GBA Case Wall Mount (Autodesk Fusion 360 design; units mm, degrees)
Autodesk Fusion 360 part; units mm, degrees
sketch "Sketch1" plane through (0, 0, 0) normal (0, 1, 0) x (1, 0, 0)
  line L0 (61, -57.75) -> (-61, -57.75)
  line L1 (-61, -57.75) -> (-61, 57.75)
  line L2 (-61, 57.75) -> (61, 57.75)
  line L3 (61, 57.75) -> (61, -57.75)
  line L4 (61, -57.75) -> (-61, 57.75) construction
  line L5 (-61, -57.75) -> (61, 57.75) construction
  dimension "d1" = 122
  dimension "d2" = 115.5
  constraint perpendicular L0 L1
  constraint parallel L0 L2
  constraint parallel L1 L3
  constraint horizontal L0
  constraint coincident L4 origin
  constraint coincident L5 origin
  measures "d1" distance of L1.end L2.end
  measures "d2" distance of L0.end L1.end
extrude "Extrude1" add sketch "Sketch1" along normal blind 2
sketch "Sketch2" plane through (0, 2, 0) normal (0, 1, 0) x (-1, 0, 0)
  line L0 (-61, -57.75) -> (61, -57.75)
  line L1 (61, -57.75) -> (61, 57.75)
  line L2 (61, 57.75) -> (-61, 57.75)
  line L3 (-61, 57.75) -> (-61, -57.75)
  line L4 (61, 57.75) -> (0.7, 57.75)
  line L5 (0.7, 57.75) -> (0.7, 19.25)
  line L6 (0.7, 19.25) -> (61, 19.25)
  line L7 (61, 19.25) -> (61, 57.75)
  line L8 (-61, 57.75) -> (-0.7, 57.75)
  line L9 (-0.7, 57.75) -> (-0.7, 19.25)
  line L10 (-0.7, 19.25) -> (-61, 19.25)
  line L11 (-61, 19.25) -> (-61, 57.75)
  line L12 (61, 19.25) -> (0.7, 19.25)
  line L13 (0.7, 19.25) -> (0.7, -19.25)
  line L14 (0.7, -19.25) -> (61, -19.25)
  line L15 (61, -19.25) -> (61, 19.25)
  line L16 (61, -19.25) -> (0.7, -19.25)
  line L17 (0.7, -19.25) -> (0.7, -57.75)
  line L18 (0.7, -57.75) -> (61, -57.75)
  line L19 (61, -57.75) -> (61, -19.25)
  line L20 (-61, 19.25) -> (-0.7, 19.25)
  line L21 (-0.7, 19.25) -> (-0.7, -19.25)
  line L22 (-0.7, -19.25) -> (-61, -19.25)
  line L23 (-61, -19.25) -> (-61, 19.25)
  line L24 (-61, -19.25) -> (-0.7, -19.25)
  line L25 (-0.7, -19.25) -> (-0.7, -57.75)
  line L26 (-0.7, -57.75) -> (-61, -57.75)
  line L27 (-61, -57.75) -> (-61, -19.25)
  line L28 (61, 57.75) -> (0.7, 57.75)
  line L29 (0.7, 57.75) -> (0.7, 56.25)
  line L30 (0.7, 56.25) -> (61, 56.25)
  line L31 (61, 56.25) -> (61, 57.75)
  line L32 (61, 19.25) -> (0.7, 19.25)
  line L33 (0.7, 19.25) -> (0.7, 17.75)
  line L34 (0.7, 17.75) -> (61, 17.75)
  line L35 (61, 17.75) -> (61, 19.25)
  line L36 (61, -19.25) -> (0.7, -19.25)
  line L37 (0.7, -19.25) -> (0.7, -20.75)
  line L38 (0.7, -20.75) -> (61, -20.75)
  line L39 (61, -20.75) -> (61, -19.25)
  line L40 (-61, -19.25) -> (-0.7, -19.25)
  line L41 (-0.7, -19.25) -> (-0.7, -20.75)
  line L42 (-0.7, -20.75) -> (-61, -20.75)
  line L43 (-61, -20.75) -> (-61, -19.25)
  line L44 (-61, 19.25) -> (-0.7, 19.25)
  line L45 (-0.7, 19.25) -> (-0.7, 17.75)
  line L46 (-0.7, 17.75) -> (-61, 17.75)
  line L47 (-61, 17.75) -> (-61, 19.25)
  line L48 (-61, 57.75) -> (-0.7, 57.75)
  line L49 (-0.7, 57.75) -> (-0.7, 56.25)
  line L50 (-0.7, 56.25) -> (-61, 56.25)
  line L51 (-61, 56.25) -> (-61, 57.75)
  line L52 (61, 57.75) -> (59.35, 57.75)
  line L53 (59.35, 57.75) -> (59.35, 56.25)
  line L54 (59.35, 56.25) -> (61, 56.25)
  line L55 (61, 56.25) -> (61, 57.75)
  line L56 (0.7, 57.75) -> (2.35, 57.75)
  line L57 (2.35, 57.75) -> (2.35, 56.25)
  line L58 (2.35, 56.25) -> (0.7, 56.25)
  line L59 (0.7, 56.25) -> (0.7, 57.75)
  line L60 (61, 19.25) -> (59.35, 19.25)
  line L61 (59.35, 19.25) -> (59.35, 17.75)
  line L62 (59.35, 17.75) -> (61, 17.75)
  line L63 (61, 17.75) -> (61, 19.25)
  line L64 (0.7, 19.25) -> (2.35, 19.25)
  line L65 (2.35, 19.25) -> (2.35, 17.75)
  line L66 (2.35, 17.75) -> (0.7, 17.75)
  line L67 (0.7, 17.75) -> (0.7, 19.25)
  line L68 (61, -19.25) -> (59.35, -19.25)
  line L69 (59.35, -19.25) -> (59.35, -20.75)
  line L70 (59.35, -20.75) -> (61, -20.75)
  line L71 (61, -20.75) -> (61, -19.25)
  line L72 (0.7, -19.25) -> (2.35, -19.25)
  line L73 (2.35, -19.25) -> (2.35, -20.75)
  line L74 (2.35, -20.75) -> (0.7, -20.75)
  line L75 (0.7, -20.75) -> (0.7, -19.25)
  line L76 (-0.7, -19.25) -> (-2.35, -19.25)
  line L77 (-2.35, -19.25) -> (-2.35, -20.75)
  line L78 (-2.35, -20.75) -> (-0.7, -20.75)
  line L79 (-0.7, -20.75) -> (-0.7, -19.25)
  line L80 (-61, -19.25) -> (-59.35, -19.25)
  line L81 (-59.35, -19.25) -> (-59.35, -20.75)
  line L82 (-59.35, -20.75) -> (-61, -20.75)
  line L83 (-61, -20.75) -> (-61, -19.25)
  line L84 (-61, 19.25) -> (-59.35, 19.25)
  line L85 (-59.35, 19.25) -> (-59.35, 17.75)
  line L86 (-59.35, 17.75) -> (-61, 17.75)
  line L87 (-61, 17.75) -> (-61, 19.25)
  line L88 (-0.7, 19.25) -> (-2.35, 19.25)
  line L89 (-2.35, 19.25) -> (-2.35, 17.75)
  line L90 (-2.35, 17.75) -> (-0.7, 17.75)
  line L91 (-0.7, 17.75) -> (-0.7, 19.25)
  line L92 (-0.7, 57.75) -> (-2.35, 57.75)
  line L93 (-2.35, 57.75) -> (-2.35, 56.25)
  line L94 (-2.35, 56.25) -> (-0.7, 56.25)
  line L95 (-0.7, 56.25) -> (-0.7, 57.75)
  line L96 (-61, 57.75) -> (-59.35, 57.75)
  line L97 (-59.35, 57.75) -> (-59.35, 56.25)
  line L98 (-59.35, 56.25) -> (-61, 56.25)
  line L99 (-61, 56.25) -> (-61, 57.75)
  dimension "d5" = 60.3
  dimension "d6" = 38.5
  dimension "d7" = 60.3
  dimension "d8" = 38.5
  dimension "d9" = 60.3
  dimension "d10" = 38.5
  dimension "d11" = 38.5
  dimension "d12" = 60.3
  dimension "d13" = 38.5
  dimension "d14" = 60.3
  dimension "d15" = 60.3
  dimension "d16" = 38.5
  dimension "d17" = 1.5
  dimension "d18" = 60.3
  dimension "d19" = 1.5
  dimension "d20" = 60.3
  dimension "d21" = 1.5
  dimension "d22" = 60.3
  dimension "d23" = 1.5
  dimension "d24" = 60.3
  dimension "d25" = 1.5
  dimension "d26" = 60.3
  dimension "d27" = 1.5
  dimension "d30" = 1.65
  dimension "d31" = 1.5
  dimension "d32" = 1.65
  dimension "d33" = 1.5
  dimension "d34" = 1.5
  dimension "d35" = 1.65
  dimension "d36" = 1.5
  dimension "d37" = 1.65
  dimension "d38" = 1.65
  dimension "d39" = 1.65
  dimension "d40" = 1.65
  dimension "d41" = 1.5
  dimension "d42" = 1.65
  dimension "d43" = 1.65
  dimension "d44" = 1.5
  dimension "d45" = 1.65
  dimension "d46" = 1.65
  dimension "d47" = 1.5
  dimension "d48" = 1.65
  constraint horizontal L4
  constraint vertical L5
  constraint horizontal L6
  constraint vertical L7
  constraint coincident L1.end L2.start
  constraint horizontal L8
  constraint vertical L9
  constraint horizontal L10
  constraint vertical L11
  constraint coincident L2.end L3.start
  constraint horizontal L12
  constraint vertical L13
  constraint horizontal L14
  constraint vertical L15
  constraint horizontal L16
  constraint vertical L17
  constraint horizontal L18
  constraint vertical L19
  constraint horizontal L20
  constraint vertical L21
  constraint horizontal L22
  constraint vertical L23
  constraint horizontal L24
  constraint vertical L25
  constraint horizontal L26
  constraint vertical L27
  constraint horizontal L28
  constraint vertical L29
  constraint horizontal L30
  constraint vertical L31
  constraint horizontal L32
  constraint vertical L33
  constraint horizontal L34
  constraint vertical L35
  constraint horizontal L36
  constraint vertical L37
  constraint horizontal L38
  constraint vertical L39
  constraint horizontal L40
  constraint vertical L41
  constraint horizontal L42
  constraint vertical L43
  constraint horizontal L44
  constraint vertical L45
  constraint horizontal L46
  constraint vertical L47
  constraint horizontal L48
  constraint vertical L49
  constraint horizontal L50
  constraint vertical L51
  constraint horizontal L52
  constraint vertical L53
  constraint horizontal L54
  constraint vertical L55
  constraint horizontal L56
  constraint vertical L57
  constraint horizontal L58
  constraint vertical L59
  constraint horizontal L60
  constraint vertical L61
  constraint horizontal L62
  constraint vertical L63
  constraint horizontal L64
  constraint vertical L65
  constraint horizontal L66
  constraint vertical L67
  constraint horizontal L68
  constraint vertical L69
  constraint horizontal L70
  constraint vertical L71
  constraint horizontal L72
  constraint vertical L73
  constraint horizontal L74
  constraint vertical L75
  constraint horizontal L76
  constraint vertical L77
  constraint horizontal L78
  constraint vertical L79
  constraint horizontal L80
  constraint vertical L81
  constraint horizontal L82
  constraint vertical L83
  constraint horizontal L84
  constraint vertical L85
  constraint horizontal L86
  constraint vertical L87
  constraint horizontal L88
  constraint vertical L89
  constraint horizontal L90
  constraint vertical L91
  constraint horizontal L92
  constraint vertical L93
  constraint horizontal L94
  constraint vertical L95
  constraint horizontal L96
  constraint vertical L97
  constraint horizontal L98
  constraint vertical L99
  measures "d5" distance of L1.end L4.end
  measures "d6" distance of L1.end L6.end
  measures "d7" distance of L2.end L8.end
  measures "d8" distance of L2.end L10.end
  measures "d9" distance of L6.end L5.end
  measures "d10" distance of L6.end L14.end
  measures "d11" distance of L14.end L0.end
  measures "d12" distance of L14.end L13.end
  measures "d13" distance of L10.end L22.end
  measures "d14" distance of L10.end L9.end
  measures "d15" distance of L22.end L21.end
  measures "d16" distance of L22.end L0.start
  measures "d17" distance of L1.end L30.end
  measures "d18" distance of L6.end L5.end
  measures "d19" distance of L6.end L34.end
  measures "d20" distance of L14.end L13.end
  measures "d21" distance of L14.end L38.end
  measures "d22" distance of L22.end L21.end
  measures "d23" distance of L22.end L42.end
  measures "d24" distance of L10.end L9.end
  measures "d25" distance of L10.end L46.end
  measures "d26" distance of L2.end L8.end
  measures "d27" distance of L2.end L50.end
  measures "d30" distance of L1.end L52.end
  measures "d31" distance of L1.end L30.end
  measures "d32" distance of L4.end L56.end
  measures "d33" distance of L4.end L29.end
  measures "d34" distance of L6.end L34.end
  measures "d35" distance of L6.end L60.end
  measures "d36" distance of L5.end L33.end
  measures "d37" distance of L5.end L64.end
  measures "d38" distance of L14.end L68.end
  measures "d39" distance of L13.end L72.end
  measures "d40" distance of L21.end L76.end
  measures "d41" distance of L21.end L41.end
  measures "d42" distance of L22.end L80.end
  measures "d43" distance of L10.end L84.end
  measures "d44" distance of L10.end L46.end
  measures "d45" distance of L9.end L88.end
  measures "d46" distance of L8.end L92.end
  measures "d47" distance of L8.end L49.end
  measures "d48" distance of L2.end L96.end
extrude "Extrude2" add sketch "Sketch2" along normal blind 7.6 contours L22 L24 L40 L42 L77 L81 | L14 L16 L36 L38 L69 L73 | L10 L20 L44 L46 L85 L89 | L6 L12 L32 L34 L61 L65 | L2 L8 L48 L50 L93 L97 | L2 L4 L28 L30 L53 L57
sketch "Sketch3" plane through (0, 0, 56.25) normal (0, 0, -1) x (-1, 0, 0)
  line L0 (-59.35, 2) -> (-2.35, 2)
  line L1 (-2.35, 2) -> (-2.35, 9.6)
  line L2 (-2.35, 9.6) -> (-59.35, 9.6)
  line L3 (-59.35, 9.6) -> (-59.35, 2)
  line L4 (-59.35, 9.6) -> (-57.2, 9.6)
  circle A0 centre (-56.2, 7.3) radius 1
  line L5 (-2.35, 9.6) -> (-5.5, 9.6)
  circle A1 centre (-5.5, 7.3) radius 1
  dimension "d49" = 2.15
  dimension "d55" = 2
  dimension "d58" = 3.15
  dimension "d59" = 2.3
  dimension "d60" = 2
  constraint coincident L2.end L3.start
  constraint coincident L1.end L2.start
  measures "d49" distance of L2.end L4.end
  measures "d55" diameter of A0
  measures "d58" distance of L1.end L5.end
  measures "d59" distance of L5.end A1.centre
  measures "d60" diameter of A1
ref_plane "WorkPlane1" through (30.85, 5.8, 54.25) normal (0, 0, -1) x (-1, 0, 0)
sketch "Sketch4" plane through (30.85, 5.8, 54.25) normal (0, 0, -1) x (1, 0, 0)
  circle A0 centre (-25.35, -1.5) radius 0.5
  circle A1 centre (25.35, -1.5) radius 0.5
  point P0 (-25.35, -1.5)
  point P1 (25.35, -1.5)
  dimension "d62" = 1
  dimension "d63" = 1
  constraint coincident P0 A0.centre
  constraint coincident P1 A1.centre
  measures "d62" diameter of A0
  measures "d63" diameter of A1
loft "Loft1" add profiles "Sketch3", "Sketch4" section 1 contours A0 section 2 contours A1
loft "Loft2" add profiles "Sketch3", "Sketch4" section 1 contours A1 section 2 contours A0
sketch "Sketch5" plane through (0, 0, 17.75) normal (0, 0, -1) x (-1, 0, 0)
  line L0 (-59.35, 2) -> (-2.35, 2)
  line L1 (-2.35, 2) -> (-2.35, 9.6)
  line L2 (-2.35, 9.6) -> (-59.35, 9.6)
  line L3 (-59.35, 9.6) -> (-59.35, 2)
  line L4 (-59.35, 9.6) -> (-56.2, 9.6)
  line L5 (-56.2, 9.6) -> (-56.2, 7.3)
  line L6 (-2.35, 9.6) -> (-5.5, 9.6)
  line L7 (-5.5, 9.6) -> (-5.5, 7.3)
  circle A0 centre (-56.2, 7.3) radius 1
  circle A1 centre (-5.5, 7.3) radius 1
  dimension "d64" = 3.15
  dimension "d65" = 2.3
  dimension "d66" = 3.15
  dimension "d67" = 2.3
  dimension "d68" = 2
  dimension "d69" = 2
  constraint coincident L2.end L3.start
  constraint coincident L1.end L2.start
  constraint coincident L5.end A0.centre
  constraint coincident L7.end A1.centre
  measures "d64" distance of L2.end L4.end
  measures "d65" distance of L4.end L5.end
  measures "d66" distance of L1.end L6.end
  measures "d67" distance of L6.end L7.end
  measures "d68" diameter of A0
  measures "d69" diameter of A1
sketch "Sketch6" plane through (0, 0, -20.75) normal (0, 0, -1) x (-1, 0, 0)
  line L0 (-59.35, 2) -> (-2.35, 2)
  line L1 (-2.35, 2) -> (-2.35, 9.6)
  line L2 (-2.35, 9.6) -> (-59.35, 9.6)
  line L3 (-59.35, 9.6) -> (-59.35, 2)
  line L4 (-59.35, 9.6) -> (-56.2, 9.6)
  line L5 (-56.2, 9.6) -> (-56.2, 7.3)
  circle A0 centre (-56.2, 7.3) radius 1
  circle A1 centre (-5.5, 7.3) radius 1
  circle A2 centre (-5.5, 7.3) radius 1
  circle A3 centre (-5.5, 7.3) radius 1
  point P0 (-56.2, 7.3)
  point P1 (-55.2, 7.3)
  point P2 (-5.5, 7.3)
  dimension "d70" = 3.15
  constraint coincident L2.end L3.start
  constraint coincident P0 L5.end
  constraint perpendicular L2 L5
  constraint coincident A0 P1
  constraint coincident P2 A1.centre
  measures "d70" distance of L2.end L4.end
sketch "Sketch7" plane through (0, 0, 56.25) normal (0, 0, -1) x (-1, 0, 0)
  line L0 (2.35, 2) -> (59.35, 2)
  line L1 (59.35, 2) -> (59.35, 9.6)
  line L2 (59.35, 9.6) -> (2.35, 9.6)
  line L3 (2.35, 9.6) -> (2.35, 2)
  line L4 (2.35, 9.6) -> (5.5, 9.6)
  line L5 (5.5, 9.6) -> (5.5, 7.3)
  line L6 (59.35, 9.6) -> (56.2, 9.6)
  line L7 (56.2, 9.6) -> (56.2, 7.3)
  circle A0 centre (5.5, 7.3) radius 1
  circle A1 centre (56.2, 7.3) radius 1
  dimension "d71" = 3.15
  dimension "d72" = 2.3
  dimension "d73" = 3.15
  dimension "d74" = 2.3
  dimension "d75" = 2
  dimension "d76" = 2
  constraint coincident L2.end L3.start
  constraint coincident L1.end L2.start
  constraint coincident L5.end A0.centre
  constraint coincident L7.end A1.centre
  measures "d71" distance of L2.end L4.end
  measures "d72" distance of L4.end L5.end
  measures "d73" distance of L1.end L6.end
  measures "d74" distance of L6.end L7.end
  measures "d75" diameter of A0
  measures "d76" diameter of A1
sketch "Sketch8" plane through (0, 0, 17.75) normal (0, 0, -1) x (-1, 0, 0)
  line L0 (2.35, 2) -> (59.35, 2)
  line L1 (59.35, 2) -> (59.35, 9.6)
  line L2 (59.35, 9.6) -> (2.35, 9.6)
  line L3 (2.35, 9.6) -> (2.35, 2)
  circle A0 centre (5.5, 7.3) radius 1
  circle A1 centre (5.5, 7.3) radius 1
  circle A2 centre (56.2, 7.3) radius 1
  circle A3 centre (56.2, 7.3) radius 1
  point P0 (5.5, 7.3)
  point P1 (56.2, 7.3)
  constraint coincident P0 A0.centre
  constraint coincident P1 A2.centre
sketch "Sketch9" plane through (0, 0, -20.75) normal (0, 0, -1) x (-1, 0, 0)
  line L0 (2.35, 2) -> (59.35, 2)
  line L1 (59.35, 2) -> (59.35, 9.6)
  line L2 (59.35, 9.6) -> (2.35, 9.6)
  line L3 (2.35, 9.6) -> (2.35, 2)
  circle A0 centre (5.5, 7.3) radius 1
  circle A1 centre (5.5, 7.3) radius 1
  circle A2 centre (56.2, 7.3) radius 1
  circle A3 centre (56.2, 7.3) radius 1
  point P0 (5.5, 7.3)
  point P1 (56.2, 7.3)
  constraint coincident P0 A0.centre
  constraint coincident P1 A2.centre
ref_plane "WorkPlane2" through (30.85, 5.8, 15.75) normal (0, 0, -1) x (-1, 0, 0)
sketch "Sketch10" plane through (30.85, 5.8, 15.75) normal (0, 0, -1) x (1, 0, 0)
  circle A0 centre (25.35, -1.5) radius 0.5
  circle A1 centre (25.35, -1.5) radius 0.5
  circle A2 centre (25.35, -1.5) radius 0.5
  circle A3 centre (-25.35, -1.5) radius 0.5
  circle A4 centre (-25.35, -1.5) radius 0.5
  point P0 (25.35, -1.5)
  point P1 (-25.35, -1.5)
  constraint coincident P0 A0.centre
  constraint coincident P1 A3.centre
ref_plane "WorkPlane3" through (30.85, 5.8, -22.75) normal (0, 0, -1) x (-1, 0, 0)
sketch "Sketch11" plane through (30.85, 5.8, -22.75) normal (0, 0, -1) x (1, 0, 0)
  circle A0 centre (25.35, -1.5) radius 0.5
  circle A1 centre (25.35, -1.5) radius 0.5
  circle A2 centre (25.35, -1.5) radius 0.5
  circle A3 centre (-25.35, -1.5) radius 0.5
  circle A4 centre (-25.35, -1.5) radius 0.5
  point P0 (25.35, -1.5)
  point P1 (-25.35, -1.5)
  constraint coincident P0 A0.centre
  constraint coincident P1 A3.centre
ref_plane "WorkPlane4" through (-30.85, 5.8, 54.25) normal (0, 0, -1) x (-1, 0, 0)
sketch "Sketch12" plane through (-30.85, 5.8, 54.25) normal (0, 0, -1) x (1, 0, 0)
  circle A0 centre (25.35, -1.5) radius 0.5
  circle A1 centre (-25.35, -1.5) radius 0.5
  point P0 (25.35, -1.5)
  point P1 (-25.35, -1.5)
  dimension "d80" = 1
  dimension "d81" = 1
  constraint coincident P0 A0.centre
  constraint coincident P1 A1.centre
  measures "d80" diameter of A0
  measures "d81" diameter of A1
ref_plane "WorkPlane5" through (-30.85, 5.8, 15.75) normal (0, 0, -1) x (-1, 0, 0)
sketch "Sketch13" plane through (-30.85, 5.8, 15.75) normal (0, 0, -1) x (1, 0, 0)
  circle A0 centre (25.35, -1.5) radius 0.5
  circle A1 centre (25.35, -1.5) radius 0.5
  circle A2 centre (-25.35, -1.5) radius 0.5
  circle A3 centre (-25.35, -1.5) radius 0.5
  point P0 (25.35, -1.5)
  point P1 (-25.35, -1.5)
  constraint coincident P0 A0.centre
  constraint coincident P1 A2.centre
ref_plane "WorkPlane6" through (-30.85, 5.8, -22.75) normal (0, 0, -1) x (-1, 0, 0)
sketch "Sketch14" plane through (-30.85, 5.8, -22.75) normal (0, 0, -1) x (1, 0, 0)
  circle A0 centre (25.35, -1.5) radius 0.5
  circle A1 centre (25.35, -1.5) radius 0.5
  circle A2 centre (-25.35, -1.5) radius 0.5
  circle A3 centre (-25.35, -1.5) radius 0.5
  point P0 (25.35, -1.5)
  point P1 (-25.35, -1.5)
  constraint coincident P0 A0.centre
  constraint coincident P1 A2.centre
loft "Loft3" add profiles "Sketch5", "Sketch10" section 1 contours A0 section 2 contours A0 A1 A2
loft "Loft4" add profiles "Sketch5", "Sketch10" section 1 contours A1 section 2 contours A3 A4
loft "Loft5" add profiles "Sketch6", "Sketch11" section 1 contours A0 section 2 contours A0 A1 A2
loft "Loft6" add profiles "Sketch6", "Sketch11" section 1 contours A1 A2 A3 section 2 contours A3 A4
loft "Loft7" add profiles "Sketch7", "Sketch12" section 1 contours A0 section 2 contours A0
loft "Loft8" add profiles "Sketch7", "Sketch12" section 1 contours A1 section 2 contours A1
loft "Loft9" add profiles "Sketch8", "Sketch13" section 1 contours A0 A1 section 2 contours A0 A1
loft "Loft10" add profiles "Sketch8", "Sketch13" section 1 contours A2 A3 section 2 contours A2 A3
loft "Loft11" add profiles "Sketch9", "Sketch14" section 1 contours A0 A1 section 2 contours A0 A1
loft "Loft12" add profiles "Sketch9", "Sketch14" section 1 contours A2 A3 section 2 contours A2 A3
sketch "Sketch15" plane through (0, 0, 0) normal (0, -1, 0) x (1, 0, 0)
  line L0 (-61, -57.75) -> (61, -57.75)
  line L1 (61, -57.75) -> (61, 57.75)
  line L2 (61, 57.75) -> (-61, 57.75)
  line L3 (-61, 57.75) -> (-61, -57.75)
  line L4 (61, -57.75) -> (20.4, -57.75)
  line L5 (-61, -57.75) -> (-20.4, -57.75)
  line L6 (20.4, -57.75) -> (20.4, -34.75)
  line L7 (-20.4, -57.75) -> (-20.4, -34.75)
  circle A0 centre (20.4, -34.75) radius 1.675
  circle A1 centre (-20.4, -34.75) radius 1.675
  dimension "d84" = 40.6
  dimension "d85" = 40.6
  dimension "d86" = 23
  dimension "d87" = 23
  dimension "d88" = 3.35
  dimension "d89" = 3.35
  constraint coincident L0.end L1.start
  constraint coincident L0.start L3.end
  constraint coincident L6.end A0.centre
  constraint coincident L7.end A1.centre
  measures "d84" distance of L0.end L4.end
  measures "d85" distance of L0.start L5.end
  measures "d86" distance of L4.end L6.end
  measures "d87" distance of L5.end L7.end
  measures "d88" diameter of A0
  measures "d89" diameter of A1
sketch "Sketch16" plane through (0, 2, 0) normal (0, 1, 0) x (-1, 0, 0)
  line L0 (-2.35, -19.25) -> (-2.35, -20.75)
  line L1 (-2.35, -20.75) -> (-59.35, -20.75)
  line L2 (-59.35, -20.75) -> (-59.35, -19.25)
  line L3 (-59.35, -19.25) -> (-2.35, -19.25)
  line L4 (-59.35, 56.25) -> (-59.35, 57.75)
  line L5 (-59.35, 57.75) -> (-61, 57.75)
  line L6 (-61, 57.75) -> (-61, -57.75)
  line L7 (-61, -57.75) -> (61, -57.75)
  line L8 (61, -57.75) -> (61, 57.75)
  line L9 (61, 57.75) -> (59.35, 57.75)
  line L10 (59.35, 57.75) -> (59.35, 56.25)
  line L11 (59.35, 56.25) -> (2.35, 56.25)
  line L12 (2.35, 56.25) -> (2.35, 57.75)
  line L13 (2.35, 57.75) -> (-2.35, 57.75)
  line L14 (-2.35, 57.75) -> (-2.35, 56.25)
  line L15 (-2.35, 56.25) -> (-59.35, 56.25)
  line L16 (-59.35, 19.25) -> (-2.35, 19.25)
  line L17 (-2.35, 19.25) -> (-2.35, 17.75)
  line L18 (-2.35, 17.75) -> (-59.35, 17.75)
  line L19 (-59.35, 17.75) -> (-59.35, 19.25)
  line L20 (59.35, -19.25) -> (59.35, -20.75)
  line L21 (59.35, -20.75) -> (2.35, -20.75)
  line L22 (2.35, -20.75) -> (2.35, -19.25)
  line L23 (2.35, -19.25) -> (59.35, -19.25)
  line L24 (59.35, 19.25) -> (59.35, 17.75)
  line L25 (59.35, 17.75) -> (2.35, 17.75)
  line L26 (2.35, 17.75) -> (2.35, 19.25)
  line L27 (2.35, 19.25) -> (59.35, 19.25)
  circle A0 centre (20.4, -34.75) radius 3.35
  circle A1 centre (-20.4, -34.75) radius 3.35
  point P0 (20.4, -34.75)
  point P1 (-20.4, -34.75)
  dimension "d90" = 6.7
  dimension "d91" = 6.7
  constraint coincident P0 A0.centre
  constraint coincident P1 A1.centre
  measures "d90" diameter of A0
  measures "d91" diameter of A1
loft "Loft13" cut profiles "Sketch16", "Sketch15" section 1 contours A0 section 2 contours A1
loft "Loft14" cut profiles "Sketch16", "Sketch15" section 1 contours A1 section 2 contours A0
sketch "Sketch17" plane through (0, 0, 0) normal (0, -1, 0) x (1, 0, 0)
  circle A0 centre (20.4, -34.75) radius 1.675
  circle A1 centre (-20.4, -34.75) radius 1.675
  line L0 (-61, -57.75) -> (61, -57.75)
  line L1 (61, -57.75) -> (61, 57.75)
  line L2 (61, 57.75) -> (-61, 57.75)
  line L3 (-61, 57.75) -> (-61, -57.75)
  line L4 (-59, 55.75) -> (59, 55.75)
  line L5 (59, 55.75) -> (59, -55.75)
  line L6 (59, -55.75) -> (-59, -55.75)
  line L7 (-59, -55.75) -> (-59, 55.75)
  line L8 (-10, 17.3205) -> (10, 17.3205)
  line L9 (10, 17.3205) -> (20, 0)
  line L10 (20, 0) -> (10, -17.3205)
  line L11 (10, -17.3205) -> (-10, -17.3205)
  line L12 (-10, -17.3205) -> (-20, 0)
  line L13 (-20, 0) -> (-10, 17.3205)
  line L14 (22.8868, 0) -> (11.4434, 19.8205)
  line L15 (11.4434, 19.8205) -> (-11.4434, 19.8205)
  line L16 (-11.4434, 19.8205) -> (-22.8868, 0)
  line L17 (-22.8868, 0) -> (-11.4434, -19.8205)
  line L18 (-11.4434, -19.8205) -> (11.4434, -19.8205)
  line L19 (11.4434, -19.8205) -> (22.8868, 0)
  line L20 (50, -17.3205) -> (30, -17.3205)
  line L21 (60, 0) -> (50, -17.3205)
  line L22 (50, 17.3205) -> (60, 0)
  line L23 (30, 17.3205) -> (50, 17.3205)
  line L24 (20, 0) -> (30, 17.3205)
  line L25 (30, -17.3205) -> (20, 0)
  line L26 (17.1132, 0) -> (28.5566, -19.8205)
  line L27 (28.5566, -19.8205) -> (51.4434, -19.8205)
  line L28 (51.4434, -19.8205) -> (62.8868, 0)
  line L29 (62.8868, 0) -> (51.4434, 19.8205)
  line L30 (51.4434, 19.8205) -> (28.5566, 19.8205)
  line L31 (28.5566, 19.8205) -> (17.1132, 0)
  line L32 (-30, -17.3205) -> (-50, -17.3205)
  line L33 (-20, 0) -> (-30, -17.3205)
  line L34 (-30, 17.3205) -> (-20, 0)
  line L35 (-50, 17.3205) -> (-30, 17.3205)
  line L36 (-60, 0) -> (-50, 17.3205)
  line L37 (-50, -17.3205) -> (-60, 0)
  line L38 (-62.8868, 0) -> (-51.4434, -19.8205)
  line L39 (-51.4434, -19.8205) -> (-28.5566, -19.8205)
  line L40 (-28.5566, -19.8205) -> (-17.1132, 0)
  line L41 (-17.1132, 0) -> (-28.5566, 19.8205)
  line L42 (-28.5566, 19.8205) -> (-51.4434, 19.8205)
  line L43 (-51.4434, 19.8205) -> (-62.8868, 0)
  line L44 (30, -51.9615) -> (10, -51.9615)
  line L45 (40, -34.641) -> (30, -51.9615)
  line L46 (30, -17.3205) -> (40, -34.641)
  line L47 (10, -17.3205) -> (30, -17.3205)
  line L48 (0, -34.641) -> (10, -17.3205)
  line L49 (10, -51.9615) -> (0, -34.641)
  line L50 (-2.8868, -34.641) -> (8.5566, -54.4615)
  line L51 (8.5566, -54.4615) -> (31.4434, -54.4615)
  line L52 (31.4434, -54.4615) -> (42.8868, -34.641)
  line L53 (42.8868, -34.641) -> (31.4434, -14.8205)
  line L54 (31.4434, -14.8205) -> (8.5566, -14.8205)
  line L55 (8.5566, -14.8205) -> (-2.8868, -34.641)
  line L56 (-10, -51.9615) -> (-30, -51.9615)
  line L57 (0, -34.641) -> (-10, -51.9615)
  line L58 (-10, -17.3205) -> (0, -34.641)
  line L59 (-30, -17.3205) -> (-10, -17.3205)
  line L60 (-40, -34.641) -> (-30, -17.3205)
  line L61 (-30, -51.9615) -> (-40, -34.641)
  line L62 (-42.8868, -34.641) -> (-31.4434, -54.4615)
  line L63 (-31.4434, -54.4615) -> (-8.5566, -54.4615)
  line L64 (-8.5566, -54.4615) -> (2.8868, -34.641)
  line L65 (2.8868, -34.641) -> (-8.5566, -14.8205)
  line L66 (-8.5566, -14.8205) -> (-31.4434, -14.8205)
  line L67 (-31.4434, -14.8205) -> (-42.8868, -34.641)
  line L68 (-50, -51.9615) -> (-70, -51.9615)
  line L69 (-40, -34.641) -> (-50, -51.9615)
  line L70 (-50, -17.3205) -> (-40, -34.641)
  line L71 (-70, -17.3205) -> (-50, -17.3205)
  line L72 (-80, -34.641) -> (-70, -17.3205)
  line L73 (-70, -51.9615) -> (-80, -34.641)
  line L74 (-82.8868, -34.641) -> (-71.4434, -54.4615)
  line L75 (-71.4434, -54.4615) -> (-48.5566, -54.4615)
  line L76 (-48.5566, -54.4615) -> (-37.1132, -34.641)
  line L77 (-37.1132, -34.641) -> (-48.5566, -14.8205)
  line L78 (-48.5566, -14.8205) -> (-71.4434, -14.8205)
  line L79 (-71.4434, -14.8205) -> (-82.8868, -34.641)
  line L80 (-10, 17.3205) -> (-30, 17.3205)
  line L81 (0, 34.641) -> (-10, 17.3205)
  line L82 (-10, 51.9615) -> (0, 34.641)
  line L83 (-30, 51.9615) -> (-10, 51.9615)
  line L84 (-40, 34.641) -> (-30, 51.9615)
  line L85 (-30, 17.3205) -> (-40, 34.641)
  line L86 (-42.8868, 34.641) -> (-31.4434, 14.8205)
  line L87 (-31.4434, 14.8205) -> (-8.5566, 14.8205)
  line L88 (-8.5566, 14.8205) -> (2.8868, 34.641)
  line L89 (2.8868, 34.641) -> (-8.5566, 54.4615)
  line L90 (-8.5566, 54.4615) -> (-31.4434, 54.4615)
  line L91 (-31.4434, 54.4615) -> (-42.8868, 34.641)
  line L92 (30, 17.3205) -> (10, 17.3205)
  line L93 (40, 34.641) -> (30, 17.3205)
  line L94 (30, 51.9615) -> (40, 34.641)
  line L95 (10, 51.9615) -> (30, 51.9615)
  line L96 (0, 34.641) -> (10, 51.9615)
  line L97 (10, 17.3205) -> (0, 34.641)
  line L98 (-2.8868, 34.641) -> (8.5566, 14.8205)
  line L99 (8.5566, 14.8205) -> (31.4434, 14.8205)
  line L100 (31.4434, 14.8205) -> (42.8868, 34.641)
  line L101 (42.8868, 34.641) -> (31.4434, 54.4615)
  line L102 (31.4434, 54.4615) -> (8.5566, 54.4615)
  line L103 (8.5566, 54.4615) -> (-2.8868, 34.641)
  line L104 (70, -51.9615) -> (50, -51.9615)
  line L105 (80, -34.641) -> (70, -51.9615)
  line L106 (70, -17.3205) -> (80, -34.641)
  line L107 (50, -17.3205) -> (70, -17.3205)
  line L108 (40, -34.641) -> (50, -17.3205)
  line L109 (50, -51.9615) -> (40, -34.641)
  line L110 (37.1132, -34.641) -> (48.5566, -54.4615)
  line L111 (48.5566, -54.4615) -> (71.4434, -54.4615)
  line L112 (71.4434, -54.4615) -> (82.8868, -34.641)
  line L113 (82.8868, -34.641) -> (71.4434, -14.8205)
  line L114 (71.4434, -14.8205) -> (48.5566, -14.8205)
  line L115 (48.5566, -14.8205) -> (37.1132, -34.641)
  line L116 (70, 17.3205) -> (50, 17.3205)
  line L117 (80, 34.641) -> (70, 17.3205)
  line L118 (70, 51.9615) -> (80, 34.641)
  line L119 (50, 51.9615) -> (70, 51.9615)
  line L120 (40, 34.641) -> (50, 51.9615)
  line L121 (50, 17.3205) -> (40, 34.641)
  line L122 (37.1132, 34.641) -> (48.5566, 14.8205)
  line L123 (48.5566, 14.8205) -> (71.4434, 14.8205)
  line L124 (71.4434, 14.8205) -> (82.8868, 34.641)
  line L125 (82.8868, 34.641) -> (71.4434, 54.4615)
  line L126 (71.4434, 54.4615) -> (48.5566, 54.4615)
  line L127 (48.5566, 54.4615) -> (37.1132, 34.641)
  line L128 (-50, 17.3205) -> (-70, 17.3205)
  line L129 (-40, 34.641) -> (-50, 17.3205)
  line L130 (-50, 51.9615) -> (-40, 34.641)
  line L131 (-70, 51.9615) -> (-50, 51.9615)
  line L132 (-80, 34.641) -> (-70, 51.9615)
  line L133 (-70, 17.3205) -> (-80, 34.641)
  line L134 (-82.8868, 34.641) -> (-71.4434, 14.8205)
  line L135 (-71.4434, 14.8205) -> (-48.5566, 14.8205)
  line L136 (-48.5566, 14.8205) -> (-37.1132, 34.641)
  line L137 (-37.1132, 34.641) -> (-48.5566, 54.4615)
  line L138 (-48.5566, 54.4615) -> (-71.4434, 54.4615)
  line L139 (-71.4434, 54.4615) -> (-82.8868, 34.641)
  line L140 (40, -39.641) -> (0, -39.641)
  line L141 (0, -29.641) -> (40, -29.641)
  line L142 (0, -29.641) -> (-40, -29.641)
  line L143 (-40, -39.641) -> (0, -39.641)
  line L144 (31.4434, -54.4615) -> (22.3059, -70.2881)
  line L145 (8.5566, -54.4615) -> (18.0359, -70.8801)
  line L146 (48.5566, -54.4615) -> (56.7045, -68.574)
  line L147 (-8.5566, -54.4615) -> (-14.9819, -65.5904)
  line L148 (-31.4434, -54.4615) -> (-23.8752, -67.57)
  line L149 (-48.5566, -54.4615) -> (-57.938, -70.7106)
  line L150 (-48.5566, 54.4615) -> (-54.7145, 65.1274)
  line L151 (-31.4434, 54.4615) -> (-25.2103, 65.2575)
  line L152 (-8.5566, 54.4615) -> (-15.4139, 66.3387)
  line L153 (8.5566, 54.4615) -> (15.292, 66.1275)
  line L154 (31.4434, 54.4615) -> (23.4533, 68.3007)
  line L155 (48.5566, 54.4615) -> (54.2736, 64.3637)
  dimension "d92" = 118
  dimension "d93" = 111.5
  constraint perpendicular L4 L5
  constraint parallel L4 L6
  constraint parallel L5 L7
  constraint horizontal L4
  constraint coincident L110 L140.start
  constraint coincident L52 L140.start
  constraint coincident L64 L140.end
  constraint coincident L50 L140.end
  constraint horizontal L140
  constraint coincident L65 L141.start
  constraint coincident L55 L141.start
  constraint coincident L115 L141.end
  constraint coincident L53 L141.end
  constraint parallel L140 L141
  constraint coincident L77 L142.end
  constraint coincident L67 L142.end
  constraint horizontal L142
  constraint coincident L76 L143.start
  constraint coincident L62 L143.start
  constraint parallel L142 L143
  constraint parallel L52 L144
  constraint parallel L50 L145
  constraint parallel L110 L146
  constraint parallel L64 L147
  constraint parallel L62 L148
  constraint parallel L76 L149
  constraint parallel L127 L155
  constraint parallel L101 L154
  constraint parallel L103 L153
  constraint parallel L89 L152
  constraint parallel L91 L151
  constraint parallel L137 L150
  measures "d92" distance of L5.end L6.end
  measures "d93" distance of L4.end L5.end
extrude "Extrude3" cut sketch "Sketch17" against normal blind 2 contours L6 L62 L76 L148 L149 | L7 L38 L39 L62 L67 L68 L69 L70 L71 | L6 L50 L64 L145 L147 | L56 L57 L61 L143 | L7 L38 L78 | L6 L52 L110 L144 L146 | L44 L45 L49 L140 | L7 L43 L135 | L7 L16 L17 L32 L33 L34 L35 L36 L37 L66 L67 L77 L78 L86 L87 L135 L136 | L39 L67 L77 | L17 L18 L39 L40 L58 L59 L60 L142 | L5 L27 L28 L52 L53 L104 L107 L108 L109 | L7 L42 L43 L86 L91 L128 L129 L130 L131 | L18 L55 L65 | L18 L19 L26 L27 L46 L47 L48 L141 | L17 L40 L66 | L5 L28 L114 | L27 L53 L115 | L8 L9 L10 L11 L12 L13 L26 L31 L40 L41 L54 L55 L65 L66 L87 L88 L98 L99 | L4 L91 L137 L150 L151 | L42 L86 L136 | L5 L29 L123 | L5 L14 L19 L20 L21 L22 L23 L24 L25 L53 L54 L99 L100 L114 L115 L122 L123 | L19 L26 L54 | L15 L16 L41 L42 L80 L81 L82 L83 L84 L85 L98 L103 L136 L137 | L16 L41 L87 | L4 L89 L103 L152 L153 | L5 L29 L30 L100 L101 L116 L119 L120 L121 | L14 L31 L99 | L4 L101 L127 L154 L155 | L14 L15 L30 L31 L88 L89 L92 L93 L94 L95 L96 L97 L122 L127 | L15 L88 L98 | L30 L100 L122
sketch "Sketch18" plane through (0, 2, 0) normal (0, -1, 0) x (1, 0, 0)
  line L0 (59, -19.25) -> (51.7728, -19.25)
  line L1 (51.7728, -19.25) -> (51.4434, -19.8205)
  line L2 (51.4434, -19.8205) -> (48.5566, -19.8205)
  line L3 (48.5566, -19.8205) -> (48.02, -20.75)
  line L4 (48.02, -20.75) -> (59, -20.75)
  line L5 (59, -20.75) -> (59, -19.25)
named bodies: "GBA Wall Mount 6 set"
